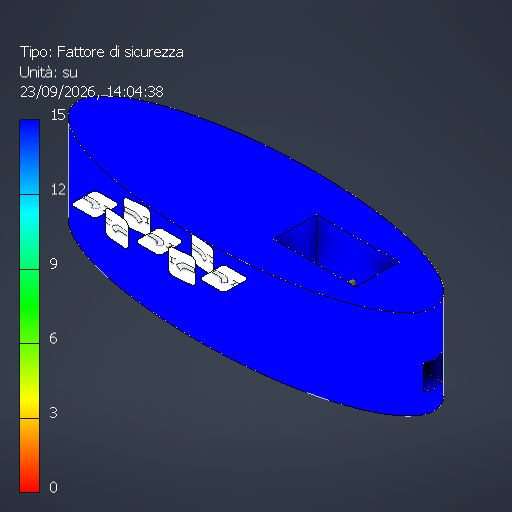
# Autodesk Inventor part: First arm
Saved by Autodesk Inventor 2026.1 (Build 301233020, 233B)
## iProperties
Created: 2026-09-23
Part Number: First arm
Material: Generico
Document SubType Name: Modeling
Designer: nuzzo
Density: 1 g/cm^3
Appearance: Default
Mass: 35.762 g
Surface Area: 187.219 cm^2
Volume: 35.762 cm^3
Author: nuzzo
Autodesk Inventor part; units mm, degrees
ref_plane "YZ Plane" through (0, 0, 0) normal (1, 0, 0) x (0, 1, 0)
ref_plane "XZ Plane" through (0, 0, 0) normal (0, 1, 0) x (-1, 0, 0)
ref_plane "XY Plane" through (0, 0, 0) normal (0, 0, 1) x (1, 0, 0)
sketch "Schizzo1" plane through (0, 0, 0) normal (0, 1, 0) x (-1, 0, 0)
  line L0 (0, 0) -> (-100, 0)
  ellipse E0 centre (-50, 0) end of major axis (-100, 0) minor radius 16.2095
  dimension "d0" = 100
  constraints: 2 end point, 2 horizontal, 1 horizontal alignment, 1 midpoint, 2 other
  measures "d0" distance of L0.start L0.end
extrude "Estrusione1" add sketch "Schizzo1" along normal blind 25
sketch "Schizzo2" plane through (0, 25, 0) normal (0, 1, 0) x (1, 0, 0)
  line L0 (0, 0) -> (100, 0)
  ellipse E0 centre (50, 0) end of major axis (100, 0) minor radius 16.2095 projected
  circle A0 centre (50, 0) radius 22.5
  line L1 (39, -6) -> (16, -6)
  line L2 (16, -6) -> (16, 6)
  line L3 (16, 6) -> (39, 6)
  line L4 (39, 6) -> (39, -6)
  line L5 (39, -6) -> (16, 6) construction
  line L6 (16, -6) -> (39, 6) construction
  line L7 (50, -16.2095) -> (50, 16.2095)
  line L8 (61, -6) -> (84, -6)
  line L9 (84, -6) -> (84, 6)
  line L10 (84, 6) -> (61, 6)
  line L11 (61, 6) -> (61, -6)
  point P0 (27.5, 0)
  dimension "d3" = 45
  dimension "d4" = 23
  dimension "d5" = 12
  constraints: 24 end point, 4 symmetric about line, 2 horizontal, 2 midpoint, 2 parallel, 1 coincident, 1 horizontal alignment, 1 perpendicular, 1 point on line, 1 vertical, 6 other
  measures "d4" distance of L2.end L3.end
  measures "d5" distance of L1.end L2.end
extrude "Estrusione2" cut sketch "Schizzo2" against normal blind 20 contours L10 L9 L0 A0 | A0 L0 L11 L10 | L8 L11 L0 A0 | A0 L0 L9 L8
sketch "Schizzo3" plane through (84, 25, -6) normal (-1, 0, 0) x (0, 0, 1)
  line L0 (0, 0) -> (12, 0) projected
  line L1 (0, -20) -> (12, 0)
  line L2 (12, 0) -> (0, 0)
  line L3 (0, 0) -> (12, -20)
  circle A0 centre (6, -10) radius 6.0078
  line L4 (8.5, -12.5078) -> (3.5, -12.5078)
  line L5 (3.5, -12.5078) -> (3.5, -19.5078)
  line L6 (3.5, -19.5078) -> (8.5, -19.5078)
  line L7 (8.5, -19.5078) -> (8.5, -12.5078)
  line L8 (8.5, -12.5078) -> (3.5, -19.5078) construction
  line L9 (3.5, -12.5078) -> (8.5, -19.5078) construction
  point P0 (6, -25)
  point P1 (6, -16.0078)
  dimension "d8" = 5
  dimension "d9" = 7
  constraints: 18 end point, 3 equal length, 3 midpoint, 1 horizontal, 1 perpendicular, 1 vertical alignment, 2 other
  measures "d8" distance of L6.end L5.end
  measures "d9" distance of L5.end L4.end
extrude "Estrusione3" cut sketch "Schizzo3" against normal through all contours L4 L3 L7 A0 L5 L1 | L1 L5 L4 | L4 L7 L3 | A0 L7 L6 L5
sketch "Schizzo5" plane through (0, 0, 0) normal (0, -1, 0) x (1, 0, 0)
  line L0 (0, 0) -> (5, 0)
  line L1 (5, 0) -> (41, 0)
  circle A0 centre (23, 0) radius 3.6
  circle A1 centre (41, 0) radius 2
  circle A2 centre (5, 0) radius 2
  line L2 (41, -2) -> (23.3216, -3.5856)
  line L3 (41, 2) -> (23.3216, 3.5856)
  line L4 (5, -2) -> (22.6784, -3.5856)
  line L5 (5, 2) -> (22.6784, 3.5856)
  point P0 (7, 0)
  point P1 (19.4, 0)
  point P2 (26.6, 0)
  point P3 (39, 0)
  point P4 (3, 0)
  dimension "d14" = 5
  dimension "d15" = 36
  dimension "d16" = 7.2
  dimension "d17" = 4
  dimension "d18" = 4
  constraints: 12 end point, 8 point on circle, 4 tangent, 3 centre point, 2 coincident, 2 horizontal, 1 midpoint
  measures "d14" distance of L0.start L0.end
  measures "d15" distance of L0.end L1.end
  measures "d16" diameter of A0
  measures "d17" diameter of A1
  measures "d18" diameter of A2
extrude "Estrusione5" cut sketch "Schizzo5" against normal blind 5
sketch "Schizzo8" plane through (0, 0, 0) normal (0, -1, 0) x (1, 0, 0)
  line L0 (84, -6) -> (84, 6) projected
  line L1 (84, 6) -> (61, 6) projected
  line L2 (61, 6) -> (61, -6) projected
  line L3 (61, -6) -> (84, -6) projected
  ellipse E0 centre (50, 0) end of major axis (100, 0) minor radius 16.2095 projected
  line L4 (84, -2.5) -> (99.4017, -2.5) projected
  line L5 (84, 2.5) -> (99.4017, 2.5) projected
  line L6 (86.369, 8.4783) -> (58.631, 8.4783)
  line L7 (58.631, 8.4783) -> (58.631, -8.4783)
  line L8 (58.631, -8.4783) -> (86.369, -8.4783)
  line L9 (86.369, -8.4783) -> (86.369, 8.4783)
  line L10 (86.369, 8.4783) -> (58.631, -8.4783) construction
  line L11 (58.631, 8.4783) -> (86.369, -8.4783) construction
  ellipse E1 centre (50, 0) end of major axis (1.6302, 0) minor radius 15.0638
  line L12 (86.369, -4.3807) -> (96.2793, -4.3807)
  line L13 (86.369, 4.3807) -> (96.2793, 4.3807)
  circle A0 centre (41, 0) radius 3.37
  arc A1 (22.6784, -3.5856) -> (23.3216, -3.5856) centre (23, 0) ccw projected
  circle A2 centre (23, 0) radius 4.97
  arc A3 (5, 2) -> (5, -2) centre (5, 0) ccw projected
  circle A4 centre (5, 0) radius 3.3698
  line L14 (40.9646, -3.3698) -> (23.4465, -4.9499)
  line L15 (40.9646, 3.3698) -> (23.4465, 4.9499)
  line L16 (5, -3.3698) -> (22.5544, -4.95)
  line L17 (5, 3.3698) -> (22.5544, 4.95)
  point P0 (0, 0)
  point P1 (72.5, 0)
  point P2 (1.6302, 0)
  dimension "d25" = 6.74
  dimension "d26" = 9.94
  constraints: 24 end point, 8 point on circle, 4 tangent, 3 centre point, 3 coincident, 2 horizontal, 2 midpoint, 2 parallel, 1 perpendicular, 1 point on line, 5 other
  measures "d25" diameter of A0
  measures "d26" diameter of A2
extrude "Estrusione6" cut sketch "Schizzo8" against normal blind 15 contours L12 E1 L13 L9 L6 L7 L8
